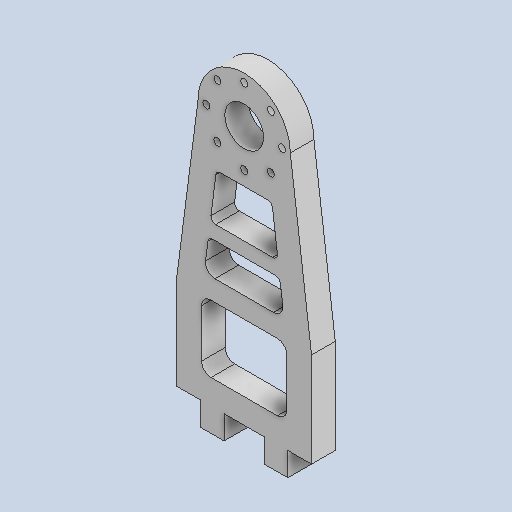
# Autodesk Inventor part: KneeSideL
Saved by Autodesk Inventor 2025.2 (Build 292293000, 293)
## iProperties
Created: 2025-06-23
Part Number: KneeSideL
Material: Generic
Document SubType Name: Modeling
Designer: ricoa
Density: 1 g/cm^3
Appearance: Default
Author: ricoa
Autodesk Inventor part; units mm, degrees
ref_plane "YZ Plane" through (0, 0, 0) normal (1, 0, 0) x (0, 1, 0)
ref_plane "XZ Plane" through (0, 0, 0) normal (0, 1, 0) x (-1, 0, 0)
ref_plane "XY Plane" through (0, 0, 0) normal (0, 0, 1) x (1, 0, 0)
sketch "Sketch1" plane through (0, 0, 0) normal (0, 0, 1) x (1, 0, 0)
  circle A0 centre (-5.6569, -5.6569) radius 0.75 projected
  circle A1 centre (-8, 0) radius 0.75 projected
  circle A2 centre (-5.6569, 5.6569) radius 0.75 projected
  circle A3 centre (0, 8) radius 0.75 projected
  circle A4 centre (5.6569, 5.6569) radius 0.75 projected
  circle A5 centre (8, 0) radius 0.75 projected
  circle A6 centre (5.6569, -5.6569) radius 0.75 projected
  circle A7 centre (0, -8) radius 0.75 projected
  line L0 (0.0217, -62.6035) -> (0.0217, -63.0506)
  line L1 (0, -54.75) -> (0.0217, -54.75)
  line L2 (4.25, -54.75) -> (4.25, -59.75)
  line L3 (9.25, -59.75) -> (9.25, -54.75)
  line L4 (-4.25, -54.75) -> (-4.25, -59.75)
  line L5 (-9.25, -59.75) -> (-9.25, -54.75)
  circle A8 centre (0, -115.5) radius 9.75 projected
  line L6 (12.25, -126.75) -> (-12.25, -126.75) projected
  line L7 (-4.25, -59.75) -> (4.25, -59.75)
  line L8 (0, -103.5) -> (-18.5, -103.5) construction
  line L9 (0, -59.75) -> (0, -59.75) construction
  line L10 (-4.25, -54.75) -> (4.25, -54.75)
  line L11 (14.25, -59.75) -> (14.25, -54.75)
  line L12 (9.25, -54.75) -> (14.25, -54.75)
  line L13 (9.25, -59.75) -> (14.25, -59.75)
  line L14 (-9.25, -59.75) -> (-14.25, -59.75)
  line L15 (-14.25, -59.75) -> (-14.25, -54.75)
  line L16 (-14.25, -54.75) -> (-9.25, -54.75)
  circle A9 centre (0, 0) radius 9.75 projected
  circle A10 centre (0, 0) radius 4 projected
  circle A11 centre (-5.6569, 5.6568) radius 0.75 projected
  circle A12 centre (-8, 0) radius 0.75 projected
  circle A13 centre (-5.6568, -5.6569) radius 0.75 projected
  circle A14 centre (0, -8) radius 0.75 projected
  circle A15 centre (5.6569, -5.6568) radius 0.75 projected
  circle A16 centre (8, 0) radius 0.75 projected
  circle A17 centre (5.6568, 5.6569) radius 0.75 projected
  circle A18 centre (0, 8) radius 0.75 projected
  circle A19 centre (0, 0) radius 4.1
  line L17 (0, 0) -> (0, -54.75)
  line L18 (-9.25, -54.75) -> (-4.25, -54.75) construction
  line L19 (4.25, -54.75) -> (9.25, -54.75) construction
  line L20 (14.25, -54.75) -> (14.25, -34.75)
  line L21 (14.25, -34.75) -> (9.75, 0)
  line L22 (-14.25, -54.75) -> (-14.25, -34.75)
  line L23 (-14.25, -34.75) -> (-9.75, 0)
  line L24 (-9.25, -59.75) -> (-4.25, -59.75)
  line L25 (4.25, -59.75) -> (9.25, -59.75)
  dimension "d12" = 5
  dimension "d49" = 5
  dimension "d50" = 5
  dimension "d53" = 8.2
  dimension "d54" = 5
  dimension "d55" = 54.75
  dimension "d57" = 20
  constraints: 50 end point, 4 perpendicular, 3 collinear, 3 horizontal, 2 midpoint, 2 point on circle, 2 point on line, 1 centre point, 1 coincident, 1 parallel, 1 symmetric about line, 1 vertical
  measures "d12" distance of L2.end L3.start
  measures "d49" distance of L5.start L14.end
  measures "d50" distance of L14.end L15.end
  measures "d53" diameter of A19
  measures "d54" distance between parallel lines of L4 L5
  measures "d55" distance of L17.start L17.end
  measures "d57" distance of L11.end L20.end
extrude "Extrusion1" add sketch "Sketch1" along normal blind 5 contours A9 | A9 L21 L20 L12 L3 L25 L2 L10 L1 L17 | L17 L10 L4 L24 L5 L16 L22 L23 A9
sketch "Sketch4" plane through (0, 0, 5) normal (0, 0, 1) x (1, 0, 0)
  circle A0 centre (0, -8) radius 0.75 projected
  line L0 (0, -8.75) -> (0, -5.75)
  line L1 (0, -8) -> (0, -11) construction
  arc A1 (9.75, 0) -> (-9.75, 0) centre (0, 0) ccw projected
  line L2 (-9.75, 0) -> (-14.25, -34.75) projected
  line L3 (-14.25, -34.75) -> (-14.25, -54.75) projected
  line L4 (-14.25, -54.75) -> (-9.25, -54.75) projected
  line L5 (-9.25, -54.75) -> (-9.25, -59.75) projected
  line L6 (-9.25, -59.75) -> (-4.25, -59.75) projected
  line L7 (-4.25, -59.75) -> (-4.25, -54.75) projected
  line L8 (-4.25, -54.75) -> (4.25, -54.75) projected
  line L9 (4.25, -54.75) -> (4.25, -59.75) projected
  line L10 (4.25, -59.75) -> (9.25, -59.75) projected
  line L11 (9.25, -59.75) -> (9.25, -54.75) projected
  line L12 (9.25, -54.75) -> (14.25, -54.75) projected
  line L13 (14.25, -54.75) -> (14.25, -34.75) projected
  line L14 (14.25, -34.75) -> (9.75, 0) projected
  circle A2 centre (0, 0) radius 4.1 projected
  circle A3 centre (-5.6569, -5.6569) radius 0.75 projected
  circle A4 centre (-8, 0) radius 0.75 projected
  circle A5 centre (-5.6569, 5.6569) radius 0.75 projected
  circle A6 centre (0, 8) radius 0.75 projected
  circle A7 centre (5.6569, 5.6569) radius 0.75 projected
  circle A8 centre (8, 0) radius 0.75 projected
  circle A9 centre (5.6569, -5.6569) radius 0.75 projected
  circle A10 centre (0, -8) radius 0.75 projected
  line L15 (9.0108, -37.3354) -> (9.0108, -47.5108)
  line L16 (7.0108, -49.5108) -> (-4.0108, -49.5108)
  line L17 (-4.0108, -49.5108) -> (-7.0108, -49.5108)
  line L18 (-9.0108, -47.5108) -> (-9.0108, -37.3354)
  line L19 (-5.0023, -11) -> (5.0023, -11)
  line L20 (0, -11) -> (0, -21) construction
  line L21 (0, -21) -> (-6.0309, -21)
  line L22 (0, -21) -> (6.0309, -21)
  line L23 (7.6656, -24.8725) -> (8.1635, -28.745)
  line L24 (-8.1635, -28.745) -> (-7.6656, -24.8725)
  line L25 (0, -21) -> (0, -24)
  line L26 (0, -24) -> (-6.6737, -24)
  line L27 (0, -24) -> (6.6737, -24)
  line L28 (0, -24) -> (0, -31)
  line L29 (0, -31) -> (-6.1798, -31)
  line L30 (0, -31) -> (6.1798, -31)
  line L31 (-7.0108, -35.3354) -> (7.0108, -35.3354)
  arc A11 (-7.0108, -35.3354) -> (-9.0108, -37.3354) centre (-7.0108, -37.3354) ccw
  arc A12 (-9.0108, -47.5108) -> (-7.0108, -49.5108) centre (-7.0108, -47.5108) ccw
  arc A13 (7.0108, -49.5108) -> (9.0108, -47.5108) centre (7.0108, -47.5108) ccw
  arc A14 (9.0108, -37.3354) -> (7.0108, -35.3354) centre (7.0108, -37.3354) ccw
  arc A15 (6.1798, -31) -> (8.1635, -28.745) centre (6.1798, -29) ccw
  arc A16 (-8.1635, -28.745) -> (-6.1798, -31) centre (-6.1798, -29) ccw
  arc A17 (-6.6737, -24) -> (-7.6656, -24.8725) centre (-6.6737, -25) ccw
  arc A18 (7.6656, -24.8725) -> (6.6737, -24) centre (6.6737, -25) ccw
  line L32 (-7.0227, -19.8725) -> (-5.9941, -11.8725)
  line L33 (5.9941, -11.8725) -> (7.0227, -19.8725)
  arc A19 (-7.0227, -19.8725) -> (-6.0309, -21) centre (-6.0309, -20) ccw
  arc A20 (-5.0023, -11) -> (-5.9941, -11.8725) centre (-5.0023, -12) ccw
  arc A21 (5.9941, -11.8725) -> (5.0023, -11) centre (5.0023, -12) ccw
  arc A22 (6.0309, -21) -> (7.0227, -19.8725) centre (6.0309, -20) ccw
  point P0 (0, 0)
  point P1 (-9.0108, -35.3354)
  point P2 (9.0108, -35.3354)
  point P3 (-5.882, -11)
  point P4 (5.882, -11)
  point P5 (-7.1677, -21)
  point P6 (7.1677, -21)
  point P7 (7.5534, -24)
  point P8 (8.4534, -31)
  dimension "d75" = 3
  dimension "d76" = 10
  dimension "d77" = 3
  dimension "d78" = 7
  dimension "d79" = 2
  dimension "d80" = 1
  dimension "d81" = 1
  constraints: 42 end point, 25 point on line, 24 point on circle, 24 tangent, 12 centre point, 9 equal radius, 4 vertical, 3 perpendicular, 2 horizontal, 1 parallel, 1 vertical alignment, 4 other
  measures "d75" distance of L1.start L1.end
  measures "d76" distance of L1.end L20.end
  measures "d77" distance of L20.end L25.end
  measures "d78" distance of L25.end L28.end
  measures "d79" radius of A11
  measures "d80" radius of A17
  measures "d81" radius of A19
extrude "Extrusion4" cut sketch "Sketch4" against normal blind 5 contours L15 A13 L16 L17 A12 L18 A11 L31 A14 | L27 A18 L23 A15 L30 L28 | L28 L29 A16 L24 A17 L26 | L19 A21 L33 A22 L22 L21 A19 L32 A20
body "Solid1"
